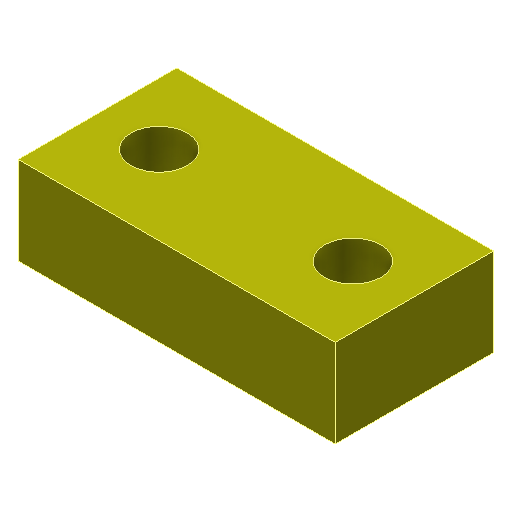
# Autodesk Inventor part: OT2-Pipette V0.6 - spring pad
Saved by Autodesk Inventor 2025.5 (Build 295498000, 498)
## iProperties
Created: 2026-11-20
Part Number: OT2-Pipette V0.6 - spring pad
Material: Generisch
Description: printed spring pad, eject variant: plate on the plunger knob, 2 M2 heat-set inserts, 2 springs to the disc
Document SubType Name: Modeling
Designer: benir
Density: 1 g/cm^3
Appearance: Yellow
Author: benir
Autodesk Inventor part; units mm, degrees
ref_plane "YZ Plane" through (0, 0, 0) normal (1, 0, 0) x (0, 1, 0)
ref_plane "y=pad_face" through (0, 74, 0) normal (0, 1, 0) x (-1, 0, 0)
sketch "pad plate" plane through (0, 74, 0) normal (0, 1, 0) x (-1, 0, 0)
  line L0 (0.8, -7.96) -> (-17.2, -7.96)
  line L1 (-17.2, -7.96) -> (-17.2, 1.04)
  line L2 (-17.2, 1.04) -> (0.8, 1.04)
  line L3 (0.8, 1.04) -> (0.8, -7.96)
  line L4 (0, -9.76) -> (0, 2.84) projected
  line L5 (4.4, 0) -> (-20.8, 0) projected
  point P0 (0, 0)
  dimension "d3" = 18
  dimension "d4" = 9
  dimension "d5" = 0.8
  dimension "d6" = 7.96
  constraints: 8 end point, 2 parallel, 1 horizontal, 1 perpendicular
  measures "d3" distance of L0.start L0.end
  measures "d4" distance of L2.end L0.start
  measures "d5" horizontal distance of point (0, 0) L2.end
  measures "d6" vertical distance of point (0, 0) L0.start
extrude "Extrusion2" add sketch "pad plate" along normal blind 5
ref_plane "y=pad_face - cut_over" through (0, 73, 0) normal (0, 1, 0) x (-1, 0, 0)
sketch "insert holes" plane through (0, 73, 0) normal (0, 1, 0) x (-1, 0, 0)
  circle A0 centre (-2.7, -3.46) radius 1.6
  circle A1 centre (-13.7, -3.46) radius 1.6
  point P0 (0, 0)
  dimension "d10" = 3.46
  dimension "d11" = 2.7
  dimension "d12" = 3.2
  dimension "d13" = 3.46
  dimension "d14" = 13.7
  dimension "d15" = 3.2
  constraints: 2 centre point
  measures "d10" vertical distance of point (0, 0) A0.centre
  measures "d11" horizontal distance of point (0, 0) A0.centre
  measures "d12" diameter of A0
  measures "d13" vertical distance of point (0, 0) A1.centre
  measures "d14" horizontal distance of point (0, 0) A1.centre
  measures "d15" diameter of A1
extrude "M2 insert holes" cut sketch "insert holes" along normal blind 7
equation "\"d3\" = pad_l + 0 * pip_x"
equation "\"d4\" = pad_w + 0 * pip_z"
equation "\"d5\" = 0.5 * pad_l - pip_x"
equation "\"d6\" = 0.5 * pad_w - pip_z"
equation "\"d7\" = pad_t"
equation "\"d10\" = -pip_z"
equation "\"d11\" = pip_x - pin_r"
equation "\"d12\" = pad_ins_d"
equation "\"d13\" = -pip_z"
equation "\"d14\" = pip_x + pin_r"
equation "\"d15\" = pad_ins_d"
equation "\"d16\" = pad_t + 2 * cut_over"
equation "\"pad_l\" = 18"
equation "\"pip_x\" = 8.2"
equation "\"pad_w\" = 9"
equation "\"pip_z\" = -3.46"
equation "\"pad_t\" = 5"
equation "\"pad_ins_d\" = 3.2"
equation "\"cut_over\" = 1"
equation "\"pin_r\" = 5.5"
body "Solid2"
